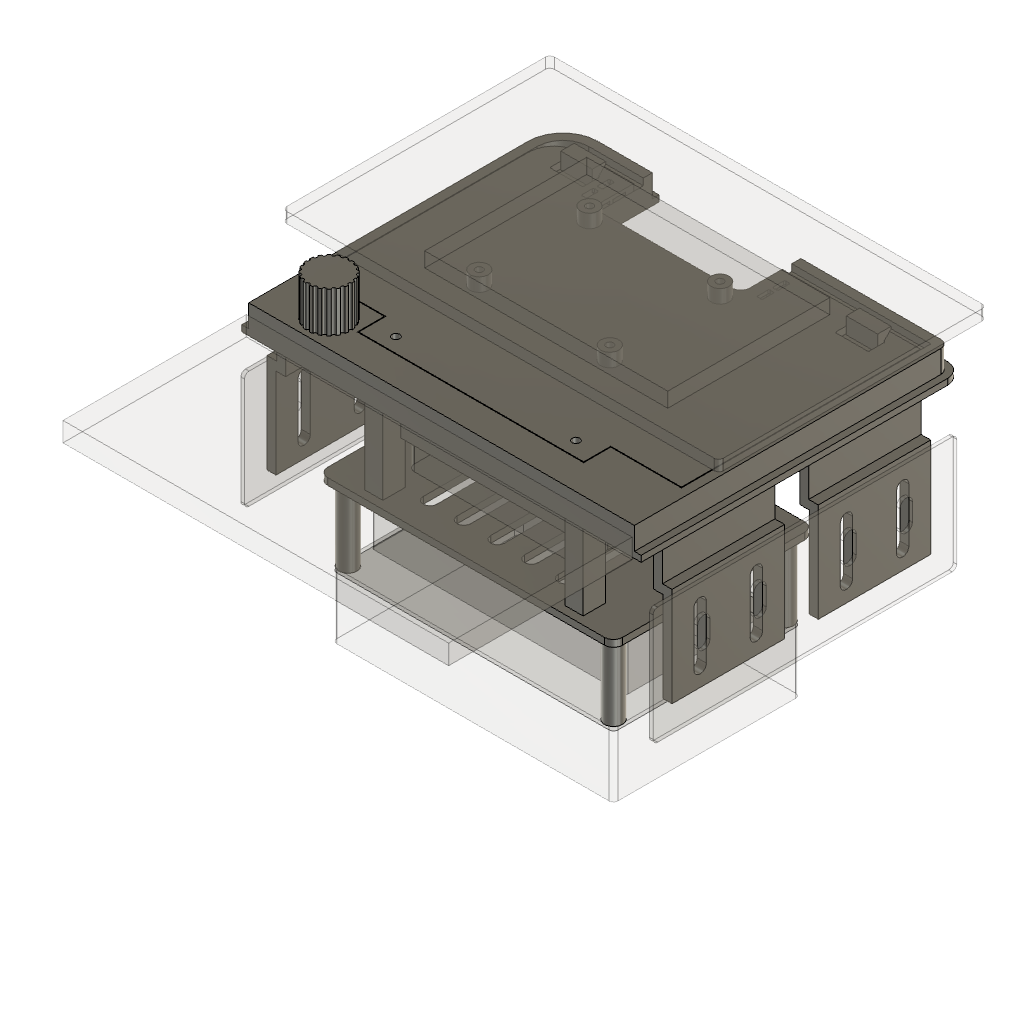
baja-dash-case (Autodesk Fusion 360 design; units mm, degrees)
part number: 2026-11-05-16-55-25-787
part number: 2026-11-05-16-55-25-887
part number: 2026-11-05-16-55-26-323
part number: 2026-11-05-16-55-27-474
part number: 2026-11-05-16-55-28-006
part number: 2026-11-05-16-55-28-400
part number: 2026-11-05-16-55-28-827
part number: 2026-11-05-16-55-29-301
part number: 2026-11-05-16-55-29-835
part number: 2026-11-05-16-55-32-602
part number: 2026-11-05-16-55-34-202
part number: 2026-11-05-16-55-34-630
part number: 2026-11-05-16-55-35-112
part number: 2026-11-05-16-55-35-616
part number: 2026-11-05-16-55-35-892
part number: 2026-11-05-16-55-36-122
Autodesk Fusion 360 part; units mm, degrees
(part 1 of 2)
ref_plane "WorkPlane1" through (0, 0, 6.35) normal (0, 0, 1) x (1, 0, 0) in component "Dash panel"
sketch "Sketch1" plane through (0, 0, 6.35) normal (0, 0, 1) x (1, 0, 0) in component "Dash panel"
  line L0 (0, 82.55) -> (171.45, 82.55)
  line L1 (171.45, 82.55) -> (171.45, 218.75)
  arc A0 (171.45, 218.75) -> (167.95, 222.25) centre (167.95, 218.75) ccw
  line L2 (167.95, 222.25) -> (15.5, 222.25)
  arc A1 (15.5, 222.25) -> (0, 206.75) centre (15.5, 206.75) ccw
  line L3 (0, 206.75) -> (0, 82.55)
extrude "Panel" add sketch "Sketch1" along normal mid plane 12.7 makes body 1 in component "Dash panel"
ref_plane "WorkPlane2" through (0, 0, 1.35) normal (0, 0, 1) x (1, 0, 0) in component "Dash panel"
sketch "Sketch2" plane through (0, 0, 1.35) normal (0, 0, 1) x (1, 0, 0) in component "Dash panel"
  line L0 (-3, 82.55) -> (174.45, 82.55)
  line L1 (174.45, 82.55) -> (174.45, 218.75)
  arc A0 (174.45, 218.75) -> (167.95, 225.25) centre (167.95, 218.75) ccw
  line L2 (167.95, 225.25) -> (-3, 225.25)
  line L3 (-3, 225.25) -> (-3, 82.55)
extrude "Lip" add sketch "Sketch2" along normal mid plane 2.7 bodies 1 in component "Dash panel"
ref_plane "WorkPlane3" through (0, 0, 11.7) normal (0, 0, 1) x (1, 0, 0) in component "Dash panel"
sketch "Sketch3" plane through (0, 0, 11.7) normal (0, 0, 1) x (1, 0, 0) in component "Dash panel"
  line L0 (4, 107.45) -> (35.425, 107.45)
  line L1 (35.425, 107.45) -> (35.425, 95.45)
  line L2 (35.425, 95.45) -> (136.025, 95.45)
  line L3 (136.025, 95.45) -> (136.025, 107.45)
  line L4 (136.025, 107.45) -> (167.45, 107.45)
  line L5 (167.45, 107.45) -> (167.45, 218.25)
  line L6 (167.45, 218.25) -> (15.5, 218.25)
  arc A0 (15.5, 218.25) -> (4, 206.75) centre (15.5, 206.75) ccw
  line L7 (4, 206.75) -> (4, 107.45)
extrude "Carrier pocket" cut sketch "Sketch3" along normal mid plane 4 bodies 1 in component "Dash panel"
ref_plane "WorkPlane4" through (22.3, 0, 0) normal (1, 0, 0) x (0, 1, 0) in component "Dash panel"
sketch "Sketch4" plane through (22.3, 0, 0) normal (1, 0, 0) x (0, 0, -1) in component "Dash panel"
  line L0 (-9.2, 205.95) -> (-9.2, 208.95)
  line L1 (-9.2, 208.95) -> (-13, 208.95)
  line L2 (-13, 208.95) -> (-16, 211.95)
  line L3 (-16, 211.95) -> (-17, 211.95)
  line L4 (-17, 211.95) -> (-17, 205.95)
  line L5 (-17, 205.95) -> (-9.2, 205.95)
extrude "Carrier hook" add sketch "Sketch4" along normal mid plane 14 bodies 1 in component "Dash panel"
ref_plane "WorkPlane5" through (149.15, 0, 0) normal (1, 0, 0) x (0, 1, 0) in component "Dash panel"
sketch "Sketch5" plane through (149.15, 0, 0) normal (1, 0, 0) x (0, 0, -1) in component "Dash panel"
  line L0 (-9.2, 205.95) -> (-9.2, 208.95)
  line L1 (-9.2, 208.95) -> (-13, 208.95)
  line L2 (-13, 208.95) -> (-16, 211.95)
  line L3 (-16, 211.95) -> (-17, 211.95)
  line L4 (-17, 211.95) -> (-17, 205.95)
  line L5 (-17, 205.95) -> (-9.2, 205.95)
extrude "Carrier hook (1)" add sketch "Sketch5" along normal mid plane 14 bodies 1 in component "Dash panel"
ref_plane "WorkPlane6" through (0, 0, 7.95) normal (0, 0, 1) x (1, 0, 0) in component "Dash panel"
sketch "Sketch6" plane through (0, 0, 7.95) normal (0, 0, 1) x (1, 0, 0) in component "Dash panel"
  circle A0 centre (45.725, 102.25) radius 2
  circle A1 centre (125.725, 102.25) radius 2
extrude "Lock screw inserts" cut sketch "Sketch6" along normal mid plane 9.5 bodies 1 in component "Dash panel"
ref_plane "WorkPlane7" through (0, 0, 6.35) normal (0, 0, 1) x (1, 0, 0) in component "Dash panel"
sketch "Sketch7" plane through (0, 0, 6.35) normal (0, 0, 1) x (1, 0, 0) in component "Dash panel"
  line L0 (43.725, 195.54) -> (101.725, 195.54)
  arc A0 (101.725, 195.54) -> (105.725, 199.54) centre (101.725, 199.54) ccw
  line L1 (105.725, 199.54) -> (105.725, 230.25)
  line L2 (105.725, 230.25) -> (39.725, 230.25)
  line L3 (39.725, 230.25) -> (39.725, 199.54)
  arc A1 (39.725, 199.54) -> (43.725, 195.54) centre (43.725, 199.54) ccw
extrude "Cable notch" cut sketch "Sketch7" along normal mid plane 14.7 bodies 1 in component "Dash panel"
ref_plane "WorkPlane8" through (0, 0, 4.6) normal (0, 0, 1) x (1, 0, 0) in component "Dash panel"
sketch "Sketch8" plane through (0, 0, 4.6) normal (0, 0, 1) x (1, 0, 0) in component "Dash panel"
  line L0 (18.5, 85.8) -> (31.5, 85.8)
  arc A0 (31.5, 85.8) -> (32.5, 86.8) centre (31.5, 86.8) ccw
  line L1 (32.5, 86.8) -> (32.5, 99.8)
  arc A1 (32.5, 99.8) -> (31.5, 100.8) centre (31.5, 99.8) ccw
  line L2 (31.5, 100.8) -> (18.5, 100.8)
  arc A2 (18.5, 100.8) -> (17.5, 99.8) centre (18.5, 99.8) ccw
  line L3 (17.5, 99.8) -> (17.5, 86.8)
  arc A3 (17.5, 86.8) -> (18.5, 85.8) centre (18.5, 86.8) ccw
extrude "Encoder pocket" cut sketch "Sketch8" along normal mid plane 11.2 bodies 1 in component "Dash panel"
ref_plane "WorkPlane9" through (0, 0, 6.35) normal (0, 0, 1) x (1, 0, 0) in component "Dash panel"
sketch "Sketch9" plane through (0, 0, 6.35) normal (0, 0, 1) x (1, 0, 0) in component "Dash panel"
  circle A0 centre (25, 93.3) radius 3.7
extrude "Encoder collar hole" cut sketch "Sketch9" along normal mid plane 14.7 bodies 1 in component "Dash panel"
ref_plane "WorkPlane10" through (0, 0, 2.75) normal (0, 0, 1) x (1, 0, 0) in component "Dash panel"
sketch "Sketch10" plane through (0, 0, 2.75) normal (0, 0, 1) x (1, 0, 0) in component "Dash panel"
  circle A0 centre (8, 103) radius 2
  circle A1 centre (8, 137) radius 2
  circle A2 centre (8, 168) radius 2
  circle A3 centre (8, 202) radius 2
  circle A4 centre (163.45, 103) radius 2
  circle A5 centre (163.45, 137) radius 2
  circle A6 centre (163.45, 168) radius 2
  circle A7 centre (163.45, 202) radius 2
  circle A8 centre (32.2, 120) radius 2
  circle A9 centre (32.2, 156) radius 2
  circle A10 centre (139.2, 120) radius 2
  circle A11 centre (139.2, 156) radius 2
extrude "Heat-set insert holes" cut sketch "Sketch10" along normal mid plane 7.5 bodies 1 in component "Dash panel"
ref_plane "WorkPlane1" through (0, 0, 11.2) normal (0, 0, 1) x (1, 0, 0) in component "Screen carrier"
sketch "Sketch1 (2)" plane through (0, 0, 11.2) normal (0, 0, 1) x (1, 0, 0) in component "Screen carrier"
  line L0 (4.3, 107.75) -> (35.725, 107.75)
  line L1 (35.725, 107.75) -> (35.725, 95.75)
  line L2 (35.725, 95.75) -> (135.725, 95.75)
  line L3 (135.725, 95.75) -> (135.725, 107.75)
  line L4 (135.725, 107.75) -> (167.15, 107.75)
  line L5 (167.15, 107.75) -> (167.15, 213.95)
  line L6 (167.15, 213.95) -> (15.5, 213.95)
  arc A0 (15.5, 213.95) -> (4.3, 202.75) centre (15.5, 202.75) ccw
  line L7 (4.3, 202.75) -> (4.3, 107.75)
extrude "Carrier" add sketch "Sketch1 (2)" along normal mid plane 3 separate body makes body 2 in component "Screen carrier"
ref_plane "WorkPlane2" through (0, 0, 15.45) normal (0, 0, 1) x (1, 0, 0) in component "Screen carrier"
sketch "Sketch2 (2)" plane through (0, 0, 15.45) normal (0, 0, 1) x (1, 0, 0) in component "Screen carrier"
  circle A0 centre (44.515, 140.54) radius 4
extrude "Screen post" add sketch "Sketch2 (2)" along normal mid plane 6.5 bodies 2 in component "Screen carrier"
ref_plane "WorkPlane3" through (0, 0, 15.45) normal (0, 0, 1) x (1, 0, 0) in component "Screen carrier"
sketch "Sketch3 (2)" plane through (0, 0, 15.45) normal (0, 0, 1) x (1, 0, 0) in component "Screen carrier"
  circle A0 centre (102.515, 140.54) radius 4
extrude "Screen post (1)" add sketch "Sketch3 (2)" along normal mid plane 6.5 bodies 2 in component "Screen carrier"
ref_plane "WorkPlane4" through (0, 0, 15.45) normal (0, 0, 1) x (1, 0, 0) in component "Screen carrier"
sketch "Sketch4 (2)" plane through (0, 0, 15.45) normal (0, 0, 1) x (1, 0, 0) in component "Screen carrier"
  circle A0 centre (44.515, 189.54) radius 4
extrude "Screen post (2)" add sketch "Sketch4 (2)" along normal mid plane 6.5 bodies 2 in component "Screen carrier"
ref_plane "WorkPlane5" through (0, 0, 15.45) normal (0, 0, 1) x (1, 0, 0) in component "Screen carrier"
sketch "Sketch5 (2)" plane through (0, 0, 15.45) normal (0, 0, 1) x (1, 0, 0) in component "Screen carrier"
  circle A0 centre (102.515, 189.54) radius 4
extrude "Screen post (3)" add sketch "Sketch5 (2)" along normal mid plane 6.5 bodies 2 in component "Screen carrier"
ref_plane "WorkPlane6" through (0, 0, 14.2) normal (0, 0, 1) x (1, 0, 0) in component "Screen carrier"
sketch "Sketch6 (2)" plane through (0, 0, 14.2) normal (0, 0, 1) x (1, 0, 0) in component "Screen carrier"
  circle A0 centre (44.515, 140.54) radius 1.6
  circle A1 centre (102.515, 140.54) radius 1.6
  circle A2 centre (44.515, 189.54) radius 1.6
  circle A3 centre (102.515, 189.54) radius 1.6
extrude "Screen screw holes" cut sketch "Sketch6 (2)" along normal mid plane 11 bodies 2 in component "Screen carrier"
ref_plane "WorkPlane7" through (0, 0, 11.2) normal (0, 0, 1) x (1, 0, 0) in component "Screen carrier"
sketch "Sketch7 (2)" plane through (0, 0, 11.2) normal (0, 0, 1) x (1, 0, 0) in component "Screen carrier"
  circle A0 centre (44.515, 140.54) radius 2.75
extrude "Screw counterbore" cut sketch "Sketch7 (2)" along normal mid plane 5 bodies 2 in component "Screen carrier"
ref_plane "WorkPlane8" through (0, 0, 11.2) normal (0, 0, 1) x (1, 0, 0) in component "Screen carrier"
sketch "Sketch8 (2)" plane through (0, 0, 11.2) normal (0, 0, 1) x (1, 0, 0) in component "Screen carrier"
  circle A0 centre (102.515, 140.54) radius 2.75
extrude "Screw counterbore (1)" cut sketch "Sketch8 (2)" along normal mid plane 5 bodies 2 in component "Screen carrier"
ref_plane "WorkPlane9" through (0, 0, 11.2) normal (0, 0, 1) x (1, 0, 0) in component "Screen carrier"
sketch "Sketch9 (2)" plane through (0, 0, 11.2) normal (0, 0, 1) x (1, 0, 0) in component "Screen carrier"
  circle A0 centre (44.515, 189.54) radius 2.75
extrude "Screw counterbore (2)" cut sketch "Sketch9 (2)" along normal mid plane 5 bodies 2 in component "Screen carrier"
ref_plane "WorkPlane10" through (0, 0, 11.2) normal (0, 0, 1) x (1, 0, 0) in component "Screen carrier"
sketch "Sketch10 (2)" plane through (0, 0, 11.2) normal (0, 0, 1) x (1, 0, 0) in component "Screen carrier"
  circle A0 centre (102.515, 189.54) radius 2.75
extrude "Screw counterbore (3)" cut sketch "Sketch10 (2)" along normal mid plane 5 bodies 2 in component "Screen carrier"
ref_plane "WorkPlane11" through (0, 0, 11.2) normal (0, 0, 1) x (1, 0, 0) in component "Screen carrier"
sketch "Sketch11" plane through (0, 0, 11.2) normal (0, 0, 1) x (1, 0, 0) in component "Screen carrier"
  line L0 (15.4, 201.45) -> (29.2, 201.45)
  arc A0 (29.2, 201.45) -> (29.7, 201.95) centre (29.2, 201.95) ccw
  line L1 (29.7, 201.95) -> (29.7, 208.45)
  arc A1 (29.7, 208.45) -> (29.2, 208.95) centre (29.2, 208.45) ccw
  line L2 (29.2, 208.95) -> (15.4, 208.95)
  arc A2 (15.4, 208.95) -> (14.9, 208.45) centre (15.4, 208.45) ccw
  line L3 (14.9, 208.45) -> (14.9, 201.95)
  arc A3 (14.9, 201.95) -> (15.4, 201.45) centre (15.4, 201.95) ccw
  line L4 (142.25, 201.45) -> (156.05, 201.45)
  arc A4 (156.05, 201.45) -> (156.55, 201.95) centre (156.05, 201.95) ccw
  line L5 (156.55, 201.95) -> (156.55, 208.45)
  arc A5 (156.55, 208.45) -> (156.05, 208.95) centre (156.05, 208.45) ccw
  line L6 (156.05, 208.95) -> (142.25, 208.95)
  arc A6 (142.25, 208.95) -> (141.75, 208.45) centre (142.25, 208.45) ccw
  line L7 (141.75, 208.45) -> (141.75, 201.95)
  arc A7 (141.75, 201.95) -> (142.25, 201.45) centre (142.25, 201.95) ccw
extrude "Hook slots" cut sketch "Sketch11" along normal mid plane 5 bodies 2 in component "Screen carrier"
ref_plane "WorkPlane12" through (0, 0, 11.2) normal (0, 0, 1) x (1, 0, 0) in component "Screen carrier"
sketch "Sketch12" plane through (0, 0, 11.2) normal (0, 0, 1) x (1, 0, 0) in component "Screen carrier"
  circle A0 centre (45.725, 102.25) radius 1.7
  circle A1 centre (125.725, 102.25) radius 1.7
extrude "Lock screw holes" cut sketch "Sketch12" along normal mid plane 5 bodies 2 in component "Screen carrier"
ref_plane "WorkPlane13" through (0, 0, 11.2) normal (0, 0, 1) x (1, 0, 0) in component "Screen carrier"
sketch "Sketch13" plane through (0, 0, 11.2) normal (0, 0, 1) x (1, 0, 0) in component "Screen carrier"
  line L0 (43.725, 195.54) -> (101.725, 195.54)
  arc A0 (101.725, 195.54) -> (105.725, 199.54) centre (101.725, 199.54) ccw
  line L1 (105.725, 199.54) -> (105.725, 218.95)
  line L2 (105.725, 218.95) -> (39.725, 218.95)
  line L3 (39.725, 218.95) -> (39.725, 199.54)
  arc A1 (39.725, 199.54) -> (43.725, 195.54) centre (43.725, 199.54) ccw
extrude "Cable notch'" cut sketch "Sketch13" along normal mid plane 5 bodies 2 in component "Screen carrier"
ref_plane "WorkPlane14" through (0, 0, 11.2) normal (0, 0, 1) x (1, 0, 0) in component "Screen carrier"
sketch "Sketch14" plane through (0, 0, 11.2) normal (0, 0, 1) x (1, 0, 0) in component "Screen carrier"
  line L0 (33.025, 197.79) -> (34.425, 197.79)
  arc A0 (34.425, 197.79) -> (34.925, 198.29) centre (34.425, 198.29) ccw
  line L1 (34.925, 198.29) -> (34.925, 202.79)
  arc A1 (34.925, 202.79) -> (34.425, 203.29) centre (34.425, 202.79) ccw
  line L2 (34.425, 203.29) -> (33.025, 203.29)
  arc A2 (33.025, 203.29) -> (32.525, 202.79) centre (33.025, 202.79) ccw
  line L3 (32.525, 202.79) -> (32.525, 198.29)
  arc A3 (32.525, 198.29) -> (33.025, 197.79) centre (33.025, 198.29) ccw
  line L4 (33.025, 204.79) -> (34.425, 204.79)
  arc A4 (34.425, 204.79) -> (34.925, 205.29) centre (34.425, 205.29) ccw
  line L5 (34.925, 205.29) -> (34.925, 209.79)
  arc A5 (34.925, 209.79) -> (34.425, 210.29) centre (34.425, 209.79) ccw
  line L6 (34.425, 210.29) -> (33.025, 210.29)
  arc A6 (33.025, 210.29) -> (32.525, 209.79) centre (33.025, 209.79) ccw
  line L7 (32.525, 209.79) -> (32.525, 205.29)
  arc A7 (32.525, 205.29) -> (33.025, 204.79) centre (33.025, 205.29) ccw
  line L8 (111.025, 197.79) -> (112.425, 197.79)
  arc A8 (112.425, 197.79) -> (112.925, 198.29) centre (112.425, 198.29) ccw
  line L9 (112.925, 198.29) -> (112.925, 202.79)
  arc A9 (112.925, 202.79) -> (112.425, 203.29) centre (112.425, 202.79) ccw
  line L10 (112.425, 203.29) -> (111.025, 203.29)
  arc A10 (111.025, 203.29) -> (110.525, 202.79) centre (111.025, 202.79) ccw
  line L11 (110.525, 202.79) -> (110.525, 198.29)
  arc A11 (110.525, 198.29) -> (111.025, 197.79) centre (111.025, 198.29) ccw
  line L12 (111.025, 204.79) -> (112.425, 204.79)
  arc A12 (112.425, 204.79) -> (112.925, 205.29) centre (112.425, 205.29) ccw
  line L13 (112.925, 205.29) -> (112.925, 209.79)
  arc A13 (112.925, 209.79) -> (112.425, 210.29) centre (112.425, 209.79) ccw
  line L14 (112.425, 210.29) -> (111.025, 210.29)
  arc A14 (111.025, 210.29) -> (110.525, 209.79) centre (111.025, 209.79) ccw
  line L15 (110.525, 209.79) -> (110.525, 205.29)
  arc A15 (110.525, 205.29) -> (111.025, 204.79) centre (111.025, 205.29) ccw
extrude "Zip-tie slots" cut sketch "Sketch14" along normal mid plane 5 bodies 2 in component "Screen carrier"
ref_plane "WorkPlane15" through (0, 0, 9.95) normal (0, 0, 1) x (1, 0, 0) in component "Screen carrier"
sketch "Sketch15" plane through (0, 0, 9.95) normal (0, 0, 1) x (1, 0, 0) in component "Screen carrier"
  line L0 (32.525, 197.79) -> (40.925, 197.79)
  line L1 (40.925, 197.79) -> (40.925, 203.29)
  line L2 (40.925, 203.29) -> (32.525, 203.29)
  line L3 (32.525, 203.29) -> (32.525, 197.79)
  line L4 (32.525, 204.79) -> (40.925, 204.79)
  line L5 (40.925, 204.79) -> (40.925, 210.29)
  line L6 (40.925, 210.29) -> (32.525, 210.29)
  line L7 (32.525, 210.29) -> (32.525, 204.79)
  line L8 (104.525, 197.79) -> (112.925, 197.79)
  line L9 (112.925, 197.79) -> (112.925, 203.29)
  line L10 (112.925, 203.29) -> (104.525, 203.29)
  line L11 (104.525, 203.29) -> (104.525, 197.79)
  line L12 (104.525, 204.79) -> (112.925, 204.79)
  line L13 (112.925, 204.79) -> (112.925, 210.29)
  line L14 (112.925, 210.29) -> (104.525, 210.29)
  line L15 (104.525, 210.29) -> (104.525, 204.79)
extrude "Zip-tie grooves" cut sketch "Sketch15" along normal mid plane 2.5 bodies 2 in component "Screen carrier"
ref_plane "WorkPlane1" through (0, 0, 22.7) normal (0, 0, 1) x (1, 0, 0) in component "Volume knob"
sketch "Sketch1 (3)" plane through (0, 0, 22.7) normal (0, 0, 1) x (1, 0, 0) in component "Volume knob"
  circle A0 centre (25, 93.3) radius 9.5
extrude "Knob" add sketch "Sketch1 (3)" along normal mid plane 18 separate body makes body 3 in component "Volume knob"
ref_plane "WorkPlane2" through (0, 0, 22.7) normal (0, 0, 1) x (1, 0, 0) in component "Volume knob"
sketch "Sketch2 (3)" plane through (0, 0, 22.7) normal (0, 0, 1) x (1, 0, 0) in component "Volume knob"
  circle A0 centre (34.5, 93.3) radius 0.8
  circle A1 centre (34.035, 96.2357) radius 0.8
  circle A2 centre (32.6857, 98.884) radius 0.8
  circle A3 centre (30.584, 100.9857) radius 0.8
  circle A4 centre (27.9357, 102.335) radius 0.8
  circle A5 centre (25, 102.8) radius 0.8
  circle A6 centre (22.0643, 102.335) radius 0.8
  circle A7 centre (19.416, 100.9857) radius 0.8
  circle A8 centre (17.3143, 98.884) radius 0.8
  circle A9 centre (15.965, 96.2357) radius 0.8
  circle A10 centre (15.5, 93.3) radius 0.8
  circle A11 centre (15.965, 90.3643) radius 0.8
  circle A12 centre (17.3143, 87.716) radius 0.8
  circle A13 centre (19.416, 85.6143) radius 0.8
  circle A14 centre (22.0643, 84.265) radius 0.8
  circle A15 centre (25, 83.8) radius 0.8
  circle A16 centre (27.9357, 84.265) radius 0.8
  circle A17 centre (30.584, 85.6143) radius 0.8
  circle A18 centre (32.6857, 87.716) radius 0.8
  circle A19 centre (34.035, 90.3643) radius 0.8
extrude "Grip" cut sketch "Sketch2 (3)" along normal mid plane 20 bodies 3 in component "Volume knob"
ref_plane "WorkPlane3" through (0, 0, 14.7) normal (0, 0, 1) x (1, 0, 0) in component "Volume knob"
sketch "Sketch3 (3)" plane through (0, 0, 14.7) normal (0, 0, 1) x (1, 0, 0) in component "Volume knob"
  circle A0 centre (25, 93.3) radius 6.25
extrude "Nut recess" cut sketch "Sketch3 (3)" along normal mid plane 4 bodies 3 in component "Volume knob"
ref_plane "WorkPlane4" through (0, 0, 16.705) normal (0, 0, 1) x (1, 0, 0) in component "Volume knob"
sketch "Sketch4 (3)" plane through (0, 0, 16.705) normal (0, 0, 1) x (1, 0, 0) in component "Volume knob"
  circle A0 centre (25, 93.3) radius 3.75
extrude "Shaft clearance" cut sketch "Sketch4 (3)" along normal mid plane 8.01 bodies 3 in component "Volume knob"
ref_plane "WorkPlane5" through (0, 0, 25.7) normal (0, 0, 1) x (1, 0, 0) in component "Volume knob"
sketch "Sketch5 (3)" plane through (0, 0, 25.7) normal (0, 0, 1) x (1, 0, 0) in component "Volume knob"
  line L0 (22.3732, 94.85) -> (27.6268, 94.85)
  arc A0 (22.3732, 94.85) -> (27.6268, 94.85) centre (25, 93.3) ccw
extrude "D bore" cut sketch "Sketch5 (3)" along normal mid plane 10 bodies 3 in component "Volume knob"
ref_plane "WorkPlane1" through (0, 120, 0) normal (0, 1, 0) x (0, 0, 1) in component "Adapter plate lower left"
sketch "Sketch1 (4)" plane through (0, 120, 0) normal (0, 1, 0) x (1, 0, 0) in component "Adapter plate lower left"
  line L0 (16, 0) -> (0, 0)
  line L1 (0, 0) -> (0, 16)
  line L2 (0, 16) -> (-4.275, 16)
  line L3 (-4.275, 16) -> (-4.275, 60)
  line L4 (-4.275, 60) -> (-0.275, 60)
  line L5 (-0.275, 60) -> (-0.275, 20)
  line L6 (-0.275, 20) -> (4, 20)
  line L7 (4, 20) -> (4, 4)
  line L8 (4, 4) -> (16, 4)
  line L9 (16, 4) -> (16, 0)
extrude "Adapter" add sketch "Sketch1 (4)" along normal mid plane 50 separate body makes body 4 in component "Adapter plate lower left"
ref_plane "WorkPlane2" through (0, 0, -2) normal (0, 0, 1) x (1, 0, 0) in component "Adapter plate lower left"
sketch "Sketch2 (4)" plane through (0, 0, -2) normal (0, 0, 1) x (1, 0, 0) in component "Adapter plate lower left"
  circle A0 centre (8, 103) radius 1.7
  circle A1 centre (8, 137) radius 1.7
extrude "Panel screw holes" cut sketch "Sketch2 (4)" along normal mid plane 6 bodies 4 in component "Adapter plate lower left"
ref_plane "WorkPlane3" through (-2.275, 0, 0) normal (1, 0, 0) x (0, 1, 0) in component "Adapter plate lower left"
sketch "Sketch3 (4)" plane through (-2.275, 0, 0) normal (1, 0, 0) x (0, 0, -1) in component "Adapter plate lower left"
  line L0 (52, 104.75) -> (28, 104.75)
  arc A0 (28, 110.25) -> (28, 104.75) centre (28, 107.5) ccw
  line L1 (28, 110.25) -> (52, 110.25)
  arc A1 (52, 104.75) -> (52, 110.25) centre (52, 107.5) ccw
extrude "Bracket slot" cut sketch "Sketch3 (4)" along normal mid plane 8 bodies 4 in component "Adapter plate lower left"
ref_plane "WorkPlane4" through (-2.275, 0, 0) normal (1, 0, 0) x (0, 1, 0) in component "Adapter plate lower left"
sketch "Sketch4 (4)" plane through (-2.275, 0, 0) normal (1, 0, 0) x (0, 0, -1) in component "Adapter plate lower left"
  line L0 (52, 129.75) -> (28, 129.75)
  arc A0 (28, 135.25) -> (28, 129.75) centre (28, 132.5) ccw
  line L1 (28, 135.25) -> (52, 135.25)
  arc A1 (52, 129.75) -> (52, 135.25) centre (52, 132.5) ccw
extrude "Bracket slot (1)" cut sketch "Sketch4 (4)" along normal mid plane 8 bodies 4 in component "Adapter plate lower left"
ref_plane "WorkPlane1" through (0, 185, 0) normal (0, 1, 0) x (0, 0, 1) in component "Adapter plate upper left"
sketch "Sketch1 (5)" plane through (0, 185, 0) normal (0, 1, 0) x (1, 0, 0) in component "Adapter plate upper left"
  line L0 (16, 0) -> (0, 0)
  line L1 (0, 0) -> (0, 16)
  line L2 (0, 16) -> (-4.275, 16)
  line L3 (-4.275, 16) -> (-4.275, 60)
  line L4 (-4.275, 60) -> (-0.275, 60)
  line L5 (-0.275, 60) -> (-0.275, 20)
  line L6 (-0.275, 20) -> (4, 20)
  line L7 (4, 20) -> (4, 4)
  line L8 (4, 4) -> (16, 4)
  line L9 (16, 4) -> (16, 0)
extrude "Adapter'" add sketch "Sketch1 (5)" along normal mid plane 50 separate body makes body 5 in component "Adapter plate upper left"
ref_plane "WorkPlane2" through (0, 0, -2) normal (0, 0, 1) x (1, 0, 0) in component "Adapter plate upper left"
sketch "Sketch2 (5)" plane through (0, 0, -2) normal (0, 0, 1) x (1, 0, 0) in component "Adapter plate upper left"
  circle A0 centre (8, 168) radius 1.7
  circle A1 centre (8, 202) radius 1.7
extrude "Panel screw holes'" cut sketch "Sketch2 (5)" along normal mid plane 6 bodies 5 in component "Adapter plate upper left"
ref_plane "WorkPlane3" through (-2.275, 0, 0) normal (1, 0, 0) x (0, 1, 0) in component "Adapter plate upper left"
sketch "Sketch3 (5)" plane through (-2.275, 0, 0) normal (1, 0, 0) x (0, 0, -1) in component "Adapter plate upper left"
  line L0 (52, 169.75) -> (28, 169.75)
  arc A0 (28, 175.25) -> (28, 169.75) centre (28, 172.5) ccw
  line L1 (28, 175.25) -> (52, 175.25)
  arc A1 (52, 169.75) -> (52, 175.25) centre (52, 172.5) ccw
extrude "Bracket slot'" cut sketch "Sketch3 (5)" along normal mid plane 8 bodies 5 in component "Adapter plate upper left"
ref_plane "WorkPlane4" through (-2.275, 0, 0) normal (1, 0, 0) x (0, 1, 0) in component "Adapter plate upper left"
sketch "Sketch4 (5)" plane through (-2.275, 0, 0) normal (1, 0, 0) x (0, 0, -1) in component "Adapter plate upper left"
  line L0 (52, 194.75) -> (28, 194.75)
  arc A0 (28, 200.25) -> (28, 194.75) centre (28, 197.5) ccw
  line L1 (28, 200.25) -> (52, 200.25)
  arc A1 (52, 194.75) -> (52, 200.25) centre (52, 197.5) ccw
extrude "Bracket slot (1)'" cut sketch "Sketch4 (5)" along normal mid plane 8 bodies 5 in component "Adapter plate upper left"
ref_plane "WorkPlane1" through (0, 120, 0) normal (0, 1, 0) x (0, 0, 1) in component "Adapter plate lower right"
sketch "Sketch1 (6)" plane through (0, 120, 0) normal (0, 1, 0) x (1, 0, 0) in component "Adapter plate lower right"
  line L0 (155.45, 0) -> (171.45, 0)
  line L1 (171.45, 0) -> (171.45, 16)
  line L2 (171.45, 16) -> (175.725, 16)
  line L3 (175.725, 16) -> (175.725, 60)
  line L4 (175.725, 60) -> (171.725, 60)
  line L5 (171.725, 60) -> (171.725, 20)
  line L6 (171.725, 20) -> (167.45, 20)
  line L7 (167.45, 20) -> (167.45, 4)
  line L8 (167.45, 4) -> (155.45, 4)
  line L9 (155.45, 4) -> (155.45, 0)
extrude "Adapter''" add sketch "Sketch1 (6)" along normal mid plane 50 separate body makes body 6 in component "Adapter plate lower right"
ref_plane "WorkPlane2" through (0, 0, -2) normal (0, 0, 1) x (1, 0, 0) in component "Adapter plate lower right"
sketch "Sketch2 (6)" plane through (0, 0, -2) normal (0, 0, 1) x (1, 0, 0) in component "Adapter plate lower right"
  circle A0 centre (163.45, 103) radius 1.7
  circle A1 centre (163.45, 137) radius 1.7
extrude "Panel screw holes''" cut sketch "Sketch2 (6)" along normal mid plane 6 bodies 6 in component "Adapter plate lower right"
ref_plane "WorkPlane3" through (173.725, 0, 0) normal (1, 0, 0) x (0, 1, 0) in component "Adapter plate lower right"
sketch "Sketch3 (6)" plane through (173.725, 0, 0) normal (1, 0, 0) x (0, 0, -1) in component "Adapter plate lower right"
  line L0 (52, 104.75) -> (28, 104.75)
  arc A0 (28, 110.25) -> (28, 104.75) centre (28, 107.5) ccw
  line L1 (28, 110.25) -> (52, 110.25)
  arc A1 (52, 104.75) -> (52, 110.25) centre (52, 107.5) ccw
extrude "Bracket slot''" cut sketch "Sketch3 (6)" along normal mid plane 8 bodies 6 in component "Adapter plate lower right"
ref_plane "WorkPlane4" through (173.725, 0, 0) normal (1, 0, 0) x (0, 1, 0) in component "Adapter plate lower right"
sketch "Sketch4 (6)" plane through (173.725, 0, 0) normal (1, 0, 0) x (0, 0, -1) in component "Adapter plate lower right"
  line L0 (52, 129.75) -> (28, 129.75)
  arc A0 (28, 135.25) -> (28, 129.75) centre (28, 132.5) ccw
  line L1 (28, 135.25) -> (52, 135.25)
  arc A1 (52, 129.75) -> (52, 135.25) centre (52, 132.5) ccw
extrude "Bracket slot (1)''" cut sketch "Sketch4 (6)" along normal mid plane 8 bodies 6 in component "Adapter plate lower right"
ref_plane "WorkPlane1" through (0, 185, 0) normal (0, 1, 0) x (0, 0, 1) in component "Adapter plate upper right"
sketch "Sketch1 (7)" plane through (0, 185, 0) normal (0, 1, 0) x (1, 0, 0) in component "Adapter plate upper right"
  line L0 (155.45, 0) -> (171.45, 0)
  line L1 (171.45, 0) -> (171.45, 16)
  line L2 (171.45, 16) -> (175.725, 16)
  line L3 (175.725, 16) -> (175.725, 60)
  line L4 (175.725, 60) -> (171.725, 60)
  line L5 (171.725, 60) -> (171.725, 20)
  line L6 (171.725, 20) -> (167.45, 20)
  line L7 (167.45, 20) -> (167.45, 4)
  line L8 (167.45, 4) -> (155.45, 4)
  line L9 (155.45, 4) -> (155.45, 0)
extrude "Adapter'''" add sketch "Sketch1 (7)" along normal mid plane 50 separate body makes body 7 in component "Adapter plate upper right"
ref_plane "WorkPlane2" through (0, 0, -2) normal (0, 0, 1) x (1, 0, 0) in component "Adapter plate upper right"
sketch "Sketch2 (7)" plane through (0, 0, -2) normal (0, 0, 1) x (1, 0, 0) in component "Adapter plate upper right"
  circle A0 centre (163.45, 168) radius 1.7
  circle A1 centre (163.45, 202) radius 1.7
extrude "Panel screw holes'''" cut sketch "Sketch2 (7)" along normal mid plane 6 bodies 7 in component "Adapter plate upper right"
ref_plane "WorkPlane3" through (173.725, 0, 0) normal (1, 0, 0) x (0, 1, 0) in component "Adapter plate upper right"
sketch "Sketch3 (7)" plane through (173.725, 0, 0) normal (1, 0, 0) x (0, 0, -1) in component "Adapter plate upper right"
  line L0 (52, 169.75) -> (28, 169.75)
  arc A0 (28, 175.25) -> (28, 169.75) centre (28, 172.5) ccw
  line L1 (28, 175.25) -> (52, 175.25)
  arc A1 (52, 169.75) -> (52, 175.25) centre (52, 172.5) ccw
extrude "Bracket slot'''" cut sketch "Sketch3 (7)" along normal mid plane 8 bodies 7 in component "Adapter plate upper right"
ref_plane "WorkPlane4" through (173.725, 0, 0) normal (1, 0, 0) x (0, 1, 0) in component "Adapter plate upper right"
sketch "Sketch4 (7)" plane through (173.725, 0, 0) normal (1, 0, 0) x (0, 0, -1) in component "Adapter plate upper right"
  line L0 (52, 194.75) -> (28, 194.75)
  arc A0 (28, 200.25) -> (28, 194.75) centre (28, 197.5) ccw
  line L1 (28, 200.25) -> (52, 200.25)
  arc A1 (52, 194.75) -> (52, 200.25) centre (52, 197.5) ccw
extrude "Bracket slot (1)'''" cut sketch "Sketch4 (7)" along normal mid plane 8 bodies 7 in component "Adapter plate upper right"
ref_plane "WorkPlane1" through (0, 0, -1.5) normal (0, 0, 1) x (1, 0, 0) in component "Pi case"
sketch "Sketch1 (8)" plane through (0, 0, -1.5) normal (0, 0, 1) x (1, 0, 0) in component "Pi case"
  line L0 (40.2, 105) -> (131.2, 105)
  arc A0 (131.2, 105) -> (134.2, 108) centre (131.2, 108) ccw
  line L1 (134.2, 108) -> (134.2, 168)
  arc A1 (134.2, 168) -> (131.2, 171) centre (131.2, 168) ccw
  line L2 (131.2, 171) -> (40.2, 171)
  arc A2 (40.2, 171) -> (37.2, 168) centre (40.2, 168) ccw
  line L3 (37.2, 168) -> (37.2, 108)
  arc A3 (37.2, 108) -> (40.2, 105) centre (40.2, 108) ccw
extrude "Floor" add sketch "Sketch1 (8)" along normal mid plane 3 separate body makes body 8 in component "Pi case"
ref_plane "WorkPlane2" through (0, 0, -1.5) normal (0, 0, 1) x (1, 0, 0) in component "Pi case"
sketch "Sketch2 (8)" plane through (0, 0, -1.5) normal (0, 0, 1) x (1, 0, 0) in component "Pi case"
  line L0 (30.2, 112) -> (35.2, 112)
  arc A0 (35.2, 112) -> (38.2, 115) centre (35.2, 115) ccw
  line L1 (38.2, 115) -> (38.2, 161)
  arc A1 (38.2, 161) -> (35.2, 164) centre (35.2, 161) ccw
  line L2 (35.2, 164) -> (30.2, 164)
  arc A2 (30.2, 164) -> (27.2, 161) centre (30.2, 161) ccw
  line L3 (27.2, 161) -> (27.2, 115)
  arc A3 (27.2, 115) -> (30.2, 112) centre (30.2, 115) ccw
  line L4 (136.2, 112) -> (141.2, 112)
  arc A4 (141.2, 112) -> (144.2, 115) centre (141.2, 115) ccw
  line L5 (144.2, 115) -> (144.2, 161)
  arc A5 (144.2, 161) -> (141.2, 164) centre (141.2, 161) ccw
  line L6 (141.2, 164) -> (136.2, 164)
  arc A6 (136.2, 164) -> (133.2, 161) centre (136.2, 161) ccw
  line L7 (133.2, 161) -> (133.2, 115)
  arc A7 (133.2, 115) -> (136.2, 112) centre (136.2, 115) ccw
extrude "Ears" add sketch "Sketch2 (8)" along normal mid plane 3 bodies 8 in component "Pi case"
ref_plane "WorkPlane3" through (0, 0, -1.5) normal (0, 0, 1) x (1, 0, 0) in component "Pi case"
sketch "Sketch3 (8)" plane through (0, 0, -1.5) normal (0, 0, 1) x (1, 0, 0) in component "Pi case"
  circle A0 centre (32.2, 120) radius 1.7
  circle A1 centre (32.2, 156) radius 1.7
  circle A2 centre (139.2, 120) radius 1.7
  circle A3 centre (139.2, 156) radius 1.7
extrude "Panel screw holes''''" cut sketch "Sketch3 (8)" along normal mid plane 5 bodies 8 in component "Pi case"
ref_plane "WorkPlane4" through (0, 0, -15.25) normal (0, 0, 1) x (1, 0, 0) in component "Pi case"
sketch "Sketch4 (8)" plane through (0, 0, -15.25) normal (0, 0, 1) x (1, 0, 0) in component "Pi case"
  line L0 (40.2, 105) -> (131.2, 105)
  arc A0 (131.2, 105) -> (134.2, 108) centre (131.2, 108) ccw
  line L1 (134.2, 108) -> (134.2, 168)
  arc A1 (134.2, 168) -> (131.2, 171) centre (131.2, 168) ccw
  line L2 (131.2, 171) -> (40.2, 171)
  arc A2 (40.2, 171) -> (37.2, 168) centre (40.2, 168) ccw
  line L3 (37.2, 168) -> (37.2, 108)
  arc A3 (37.2, 108) -> (40.2, 105) centre (40.2, 108) ccw
  line L4 (40.2, 107) -> (131.2, 107)
  arc A4 (131.2, 107) -> (132.2, 108) centre (131.2, 108) ccw
  line L5 (132.2, 108) -> (132.2, 168)
  arc A5 (132.2, 168) -> (131.2, 169) centre (131.2, 168) ccw
  line L6 (131.2, 169) -> (40.2, 169)
  arc A6 (40.2, 169) -> (39.2, 168) centre (40.2, 168) ccw
  line L7 (39.2, 168) -> (39.2, 108)
  arc A7 (39.2, 108) -> (40.2, 107) centre (40.2, 108) ccw
extrude "Walls" add sketch "Sketch4 (8)" along normal mid plane 25.5 contours L0 A0 L1 A1 L2 A2 L3 A3 | L4 A4 L5 A5 L6 A6 L7 A7 bodies 8 in component "Pi case"
ref_plane "WorkPlane5" through (0, 0, -16) normal (0, 0, 1) x (1, 0, 0) in component "Pi case"
sketch "Sketch5 (4)" plane through (0, 0, -16) normal (0, 0, 1) x (1, 0, 0) in component "Pi case"
  line L0 (40.2, 107) -> (131.2, 107)
  arc A0 (131.2, 107) -> (132.2, 108) centre (131.2, 108) ccw
  line L1 (132.2, 108) -> (132.2, 168)
  arc A1 (132.2, 168) -> (131.2, 169) centre (131.2, 168) ccw
  line L2 (131.2, 169) -> (40.2, 169)
  arc A2 (40.2, 169) -> (39.2, 168) centre (40.2, 168) ccw
  line L3 (39.2, 168) -> (39.2, 108)
  arc A3 (39.2, 108) -> (40.2, 107) centre (40.2, 108) ccw
extrude "Inside" cut sketch "Sketch5 (4)" along normal mid plane 26 bodies 8 in component "Pi case"
ref_plane "WorkPlane6" through (0, 0, -5.75) normal (0, 0, 1) x (1, 0, 0) in component "Pi case"
sketch "Sketch6 (3)" plane through (0, 0, -5.75) normal (0, 0, 1) x (1, 0, 0) in component "Pi case"
  circle A0 centre (46.7, 113.5) radius 3.5
  circle A1 centre (104.7, 113.5) radius 3.5
  circle A2 centre (46.7, 162.5) radius 3.5
  circle A3 centre (104.7, 162.5) radius 3.5
extrude "Standoffs" add sketch "Sketch6 (3)" along normal mid plane 6.5 bodies 8 in component "Pi case"
ref_plane "WorkPlane7" through (0, 0, -6.75) normal (0, 0, 1) x (1, 0, 0) in component "Pi case"
sketch "Sketch7 (3)" plane through (0, 0, -6.75) normal (0, 0, 1) x (1, 0, 0) in component "Pi case"
  circle A0 centre (46.7, 113.5) radius 1.8
  circle A1 centre (104.7, 113.5) radius 1.8
  circle A2 centre (46.7, 162.5) radius 1.8
  circle A3 centre (104.7, 162.5) radius 1.8
extrude "Insert holes" cut sketch "Sketch7 (3)" along normal mid plane 6.5 bodies 8 in component "Pi case"
ref_plane "WorkPlane8" through (0, 0, -1.5) normal (0, 0, 1) x (1, 0, 0) in component "Pi case"
sketch "Sketch8 (3)" plane through (0, 0, -1.5) normal (0, 0, 1) x (1, 0, 0) in component "Pi case"
  line L0 (56.2, 120) -> (95.2, 120)
  arc A0 (95.2, 120) -> (98.2, 123) centre (95.2, 123) ccw
  line L1 (98.2, 123) -> (98.2, 153)
  arc A1 (98.2, 153) -> (95.2, 156) centre (95.2, 153) ccw
  line L2 (95.2, 156) -> (56.2, 156)
  arc A2 (56.2, 156) -> (53.2, 153) centre (56.2, 153) ccw
  line L3 (53.2, 153) -> (53.2, 123)
  arc A3 (53.2, 123) -> (56.2, 120) centre (56.2, 123) ccw
extrude "Vent" cut sketch "Sketch8 (3)" along normal mid plane 5 bodies 8 in component "Pi case"
ref_plane "WorkPlane9" through (133.2, 0, 0) normal (1, 0, 0) x (0, 1, 0) in component "Pi case"
sketch "Sketch9 (3)" plane through (133.2, 0, 0) normal (1, 0, 0) x (0, 0, -1) in component "Pi case"
  line L0 (30, 112.5) -> (30, 125.5)
  arc A0 (30, 125.5) -> (29, 126.5) centre (29, 125.5) ccw
  line L1 (29, 126.5) -> (9.4, 126.5)
  arc A1 (9.4, 126.5) -> (8.4, 125.5) centre (9.4, 125.5) ccw
  line L2 (8.4, 125.5) -> (8.4, 112.5)
  arc A2 (8.4, 112.5) -> (9.4, 111.5) centre (9.4, 112.5) ccw
  line L3 (9.4, 111.5) -> (29, 111.5)
  arc A3 (29, 111.5) -> (30, 112.5) centre (29, 112.5) ccw
  line L4 (30, 130.4) -> (30, 143.4)
  arc A4 (30, 143.4) -> (29, 144.4) centre (29, 143.4) ccw
  line L5 (29, 144.4) -> (9.4, 144.4)
  arc A5 (9.4, 144.4) -> (8.4, 143.4) centre (9.4, 143.4) ccw
  line L6 (8.4, 143.4) -> (8.4, 130.4)
  arc A6 (8.4, 130.4) -> (9.4, 129.4) centre (9.4, 130.4) ccw
  line L7 (9.4, 129.4) -> (29, 129.4)
  arc A7 (29, 129.4) -> (30, 130.4) centre (29, 130.4) ccw
  line L8 (30, 148.05) -> (30, 163.55)
  arc A8 (30, 163.55) -> (29, 164.55) centre (29, 163.55) ccw
  line L9 (29, 164.55) -> (9.4, 164.55)
  arc A9 (9.4, 164.55) -> (8.4, 163.55) centre (9.4, 163.55) ccw
  line L10 (8.4, 163.55) -> (8.4, 148.05)
  arc A10 (8.4, 148.05) -> (9.4, 147.05) centre (9.4, 148.05) ccw
  line L11 (9.4, 147.05) -> (29, 147.05)
  arc A11 (29, 147.05) -> (30, 148.05) centre (29, 148.05) ccw
extrude "USB and Ethernet" cut sketch "Sketch9 (3)" along normal mid plane 4 bodies 8 in component "Pi case"
ref_plane "WorkPlane10" through (0, 170, 0) normal (0, 1, 0) x (0, 0, 1) in component "Pi case"
sketch "Sketch10 (3)" plane through (0, 170, 0) normal (0, 1, 0) x (1, 0, 0) in component "Pi case"
  line L0 (48.4, 30) -> (88.4, 30)
  arc A0 (89.4, 29) -> (88.4, 30) centre (88.4, 29) ccw
  line L1 (89.4, 29) -> (89.4, 9.4)
  arc A1 (88.4, 8.4) -> (89.4, 9.4) centre (88.4, 9.4) ccw
  line L2 (88.4, 8.4) -> (48.4, 8.4)
  arc A2 (47.4, 9.4) -> (48.4, 8.4) centre (48.4, 9.4) ccw
  line L3 (47.4, 9.4) -> (47.4, 29)
  arc A3 (48.4, 30) -> (47.4, 29) centre (48.4, 29) ccw
extrude "Power and HDMI" cut sketch "Sketch10 (3)" along normal mid plane 4 bodies 8 in component "Pi case"
ref_plane "WorkPlane11" through (38.2, 0, 0) normal (1, 0, 0) x (0, 1, 0) in component "Pi case"
sketch "Sketch11 (2)" plane through (38.2, 0, 0) normal (1, 0, 0) x (0, 0, -1) in component "Pi case"
  line L0 (17.6, 130) -> (17.6, 155)
  arc A0 (17.6, 155) -> (16.6, 156) centre (16.6, 155) ccw
  line L1 (16.6, 156) -> (9.4, 156)
  arc A1 (9.4, 156) -> (8.4, 155) centre (9.4, 155) ccw
  line L2 (8.4, 155) -> (8.4, 130)
  arc A2 (8.4, 130) -> (9.4, 129) centre (9.4, 130) ccw
  line L3 (9.4, 129) -> (16.6, 129)
  arc A3 (16.6, 129) -> (17.6, 130) centre (16.6, 130) ccw
extrude "PCIe and power button" cut sketch "Sketch11 (2)" along normal mid plane 4 bodies 8 in component "Pi case"
ref_plane "WorkPlane12" through (0, 0, -24) normal (0, 0, 1) x (1, 0, 0) in component "Pi case"
sketch "Sketch12 (2)" plane through (0, 0, -24) normal (0, 0, 1) x (1, 0, 0) in component "Pi case"
  line L0 (37.2, 97) -> (45.2, 97)
  line L1 (45.2, 97) -> (45.2, 107)
  line L2 (45.2, 107) -> (37.2, 107)
  line L3 (37.2, 107) -> (37.2, 97)
  line L4 (126.2, 97) -> (134.2, 97)
  line L5 (134.2, 97) -> (134.2, 107)
  line L6 (134.2, 107) -> (126.2, 107)
  line L7 (126.2, 107) -> (126.2, 97)
  line L8 (37.2, 169) -> (45.2, 169)
  line L9 (45.2, 169) -> (45.2, 179)
  line L10 (45.2, 179) -> (37.2, 179)
  line L11 (37.2, 179) -> (37.2, 169)
  line L12 (126.2, 169) -> (134.2, 169)
  line L13 (134.2, 169) -> (134.2, 179)
  line L14 (134.2, 179) -> (126.2, 179)
  line L15 (126.2, 179) -> (126.2, 169)
extrude "Amp posts" add sketch "Sketch12 (2)" along normal mid plane 48 bodies 8 in component "Pi case"
ref_plane "WorkPlane13" through (0, 0, -45.25) normal (0, 0, 1) x (1, 0, 0) in component "Pi case"
sketch "Sketch13 (2)" plane through (0, 0, -45.25) normal (0, 0, 1) x (1, 0, 0) in component "Pi case"
  circle A0 centre (41.2, 101) radius 2
  circle A1 centre (130.2, 101) radius 2
  circle A2 centre (41.2, 175) radius 2
  circle A3 centre (130.2, 175) radius 2
extrude "Amp post inserts" cut sketch "Sketch13 (2)" along normal mid plane 7.5 bodies 8 in component "Pi case"
ref_plane "WorkPlane1" through (0, 0, -49.5) normal (0, 0, 1) x (1, 0, 0) in component "Amp plate"
sketch "Sketch1 (9)" plane through (0, 0, -49.5) normal (0, 0, 1) x (1, 0, 0) in component "Amp plate"
  line L0 (24.2, 93.5) -> (147.2, 93.5)
  arc A0 (147.2, 93.5) -> (151.2, 97.5) centre (147.2, 97.5) ccw
  line L1 (151.2, 97.5) -> (151.2, 178.5)
  arc A1 (151.2, 178.5) -> (147.2, 182.5) centre (147.2, 178.5) ccw
  line L2 (147.2, 182.5) -> (24.2, 182.5)
  arc A2 (24.2, 182.5) -> (20.2, 178.5) centre (24.2, 178.5) ccw
  line L3 (20.2, 178.5) -> (20.2, 97.5)
  arc A3 (20.2, 97.5) -> (24.2, 93.5) centre (24.2, 97.5) ccw
extrude "Plate" add sketch "Sketch1 (9)" along normal mid plane 3 separate body makes body 9 in component "Amp plate"
ref_plane "WorkPlane2" through (0, 0, -67.25) normal (0, 0, 1) x (1, 0, 0) in component "Amp plate"
sketch "Sketch2 (9)" plane through (0, 0, -67.25) normal (0, 0, 1) x (1, 0, 0) in component "Amp plate"
  circle A0 centre (26.7, 100) radius 4
  circle A1 centre (144.7, 100) radius 4
  circle A2 centre (26.7, 176) radius 4
  circle A3 centre (144.7, 176) radius 4
extrude "Amp standoffs" add sketch "Sketch2 (9)" along normal mid plane 33.5 bodies 9 in component "Amp plate"
ref_plane "WorkPlane3" through (0, 0, -82.25) normal (0, 0, 1) x (1, 0, 0) in component "Amp plate"
sketch "Sketch3 (9)" plane through (0, 0, -82.25) normal (0, 0, 1) x (1, 0, 0) in component "Amp plate"
  circle A0 centre (26.7, 100) radius 1.6
  circle A1 centre (144.7, 100) radius 1.6
  circle A2 centre (26.7, 176) radius 1.6
  circle A3 centre (144.7, 176) radius 1.6
extrude "Amp insert holes" cut sketch "Sketch3 (9)" along normal mid plane 5.5 bodies 9 in component "Amp plate"
ref_plane "WorkPlane4" through (0, 0, -49.5) normal (0, 0, 1) x (1, 0, 0) in component "Amp plate"
sketch "Sketch4 (9)" plane through (0, 0, -49.5) normal (0, 0, 1) x (1, 0, 0) in component "Amp plate"
  circle A0 centre (41.2, 101) radius 1.7
  circle A1 centre (130.2, 101) radius 1.7
  circle A2 centre (41.2, 175) radius 1.7
  circle A3 centre (130.2, 175) radius 1.7
extrude "Post screw holes" cut sketch "Sketch4 (9)" along normal mid plane 5 bodies 9 in component "Amp plate"
ref_plane "WorkPlane5" through (0, 0, -52.75) normal (0, 0, 1) x (1, 0, 0) in component "Amp plate"
sketch "Sketch5 (5)" plane through (0, 0, -52.75) normal (0, 0, 1) x (1, 0, 0) in component "Amp plate"
  circle A0 centre (33.2, 112) radius 4
  circle A1 centre (138.2, 112) radius 4
  circle A2 centre (33.2, 164) radius 4
  circle A3 centre (138.2, 164) radius 4
extrude "Mean Well bosses" add sketch "Sketch5 (5)" along normal mid plane 4.5 bodies 9 in component "Amp plate"
ref_plane "WorkPlane6" through (0, 0, -52.25) normal (0, 0, 1) x (1, 0, 0) in component "Amp plate"
sketch "Sketch6 (4)" plane through (0, 0, -52.25) normal (0, 0, 1) x (1, 0, 0) in component "Amp plate"
  circle A0 centre (33.2, 112) radius 2
  circle A1 centre (138.2, 112) radius 2
  circle A2 centre (33.2, 164) radius 2
  circle A3 centre (138.2, 164) radius 2
extrude "Mean Well insert holes" cut sketch "Sketch6 (4)" along normal mid plane 7.5 bodies 9 in component "Amp plate"
ref_plane "WorkPlane7" through (0, 0, -49.5) normal (0, 0, 1) x (1, 0, 0) in component "Amp plate"
sketch "Sketch7 (4)" plane through (0, 0, -49.5) normal (0, 0, 1) x (1, 0, 0) in component "Amp plate"
  line L0 (52.7, 107.5) -> (52.7, 168.5)
  arc A0 (58.7, 168.5) -> (52.7, 168.5) centre (55.7, 168.5) ccw
  line L1 (58.7, 168.5) -> (58.7, 107.5)
  arc A1 (52.7, 107.5) -> (58.7, 107.5) centre (55.7, 107.5) ccw
  line L2 (67.7, 107.5) -> (67.7, 168.5)
  arc A2 (73.7, 168.5) -> (67.7, 168.5) centre (70.7, 168.5) ccw
  line L3 (73.7, 168.5) -> (73.7, 107.5)
  arc A3 (67.7, 107.5) -> (73.7, 107.5) centre (70.7, 107.5) ccw
  line L4 (82.7, 107.5) -> (82.7, 168.5)
  arc A4 (88.7, 168.5) -> (82.7, 168.5) centre (85.7, 168.5) ccw
  line L5 (88.7, 168.5) -> (88.7, 107.5)
  arc A5 (82.7, 107.5) -> (88.7, 107.5) centre (85.7, 107.5) ccw
  line L6 (97.7, 107.5) -> (97.7, 168.5)
  arc A6 (103.7, 168.5) -> (97.7, 168.5) centre (100.7, 168.5) ccw
  line L7 (103.7, 168.5) -> (103.7, 107.5)
  arc A7 (97.7, 107.5) -> (103.7, 107.5) centre (100.7, 107.5) ccw
  line L8 (112.7, 107.5) -> (112.7, 168.5)
  arc A8 (118.7, 168.5) -> (112.7, 168.5) centre (115.7, 168.5) ccw
  line L9 (118.7, 168.5) -> (118.7, 107.5)
  arc A9 (112.7, 107.5) -> (118.7, 107.5) centre (115.7, 107.5) ccw
extrude "Vents" cut sketch "Sketch7 (4)" along normal mid plane 5 bodies 9 in component "Amp plate"
ref_plane "WorkPlane1" through (0, 0, 27.69) normal (0, 0, 1) x (1, 0, 0) in component "Screen (reference)"
sketch "Sketch1 (10)" plane through (0, 0, 27.69) normal (0, 0, 1) x (1, 0, 0) in component "Screen (reference)"
  line L0 (-9.275, 108.75) -> (180.725, 108.75)
  arc A0 (180.725, 108.75) -> (182.725, 110.75) centre (180.725, 110.75) ccw
  line L1 (182.725, 110.75) -> (182.725, 225.75)
  arc A1 (182.725, 225.75) -> (180.725, 227.75) centre (180.725, 225.75) ccw
  line L2 (180.725, 227.75) -> (-9.275, 227.75)
  arc A2 (-9.275, 227.75) -> (-11.275, 225.75) centre (-9.275, 225.75) ccw
  line L3 (-11.275, 225.75) -> (-11.275, 110.75)
  arc A3 (-11.275, 110.75) -> (-9.275, 108.75) centre (-9.275, 110.75) ccw
extrude "Extrude1" add sketch "Sketch1 (10)" along normal mid plane 4.8 separate body makes body 10 in component "Screen (reference)"
ref_plane "WorkPlane2" through (0, 0, 21.995) normal (0, 0, 1) x (1, 0, 0) in component "Screen (reference)"
sketch "Sketch2 (10)" plane through (0, 0, 21.995) normal (0, 0, 1) x (1, 0, 0) in component "Screen (reference)"
  line L0 (31.765, 129.04) -> (139.765, 129.04)
  line L1 (139.765, 129.04) -> (139.765, 201.04)
  line L2 (139.765, 201.04) -> (31.765, 201.04)
  line L3 (31.765, 201.04) -> (31.765, 129.04)
extrude "Extrude2" add sketch "Sketch2 (10)" along normal mid plane 6.59 separate body makes body 11 in component "Screen (reference)"
ref_plane "WorkPlane1" through (0, 0, -9.8) normal (0, 0, 1) x (1, 0, 0) in component "Raspberry Pi 5 + DAC (reference)"
sketch "Sketch1 (11)" plane through (0, 0, -9.8) normal (0, 0, 1) x (1, 0, 0) in component "Raspberry Pi 5 + DAC (reference)"
  line L0 (46.2, 110) -> (125.2, 110)
  arc A0 (125.2, 110) -> (128.2, 113) centre (125.2, 113) ccw
  line L1 (128.2, 113) -> (128.2, 163)
  arc A1 (128.2, 163) -> (125.2, 166) centre (125.2, 163) ccw
  line L2 (125.2, 166) -> (46.2, 166)
  arc A2 (46.2, 166) -> (43.2, 163) centre (46.2, 163) ccw
  line L3 (43.2, 163) -> (43.2, 113)
  arc A3 (43.2, 113) -> (46.2, 110) centre (46.2, 113) ccw
extrude "Extrude1'" add sketch "Sketch1 (11)" along normal mid plane 1.6 separate body makes body 12 in component "Raspberry Pi 5 + DAC (reference)"
ref_plane "WorkPlane2" through (0, 0, -26.8) normal (0, 0, 1) x (1, 0, 0) in component "Raspberry Pi 5 + DAC (reference)"
sketch "Sketch2 (11)" plane through (0, 0, -26.8) normal (0, 0, 1) x (1, 0, 0) in component "Raspberry Pi 5 + DAC (reference)"
  line L0 (46.2, 110) -> (125.2, 110)
  arc A0 (125.2, 110) -> (128.2, 113) centre (125.2, 113) ccw
  line L1 (128.2, 113) -> (128.2, 163)
  arc A1 (128.2, 163) -> (125.2, 166) centre (125.2, 163) ccw
  line L2 (125.2, 166) -> (46.2, 166)
  arc A2 (46.2, 166) -> (43.2, 163) centre (46.2, 163) ccw
  line L3 (43.2, 163) -> (43.2, 113)
  arc A3 (43.2, 113) -> (46.2, 110) centre (46.2, 113) ccw
extrude "Extrude2'" add sketch "Sketch2 (11)" along normal mid plane 32.4 separate body makes body 13 in component "Raspberry Pi 5 + DAC (reference)"
ref_plane "WorkPlane1" through (0, 0, -84.8) normal (0, 0, 1) x (1, 0, 0) in component "Amp (reference)"
sketch "Sketch1 (12)" plane through (0, 0, -84.8) normal (0, 0, 1) x (1, 0, 0) in component "Amp (reference)"
  line L0 (25.2, 96.5) -> (146.2, 96.5)
  arc A0 (146.2, 96.5) -> (148.2, 98.5) centre (146.2, 98.5) ccw
  line L1 (148.2, 98.5) -> (148.2, 177.5)
  arc A1 (148.2, 177.5) -> (146.2, 179.5) centre (146.2, 177.5) ccw
  line L2 (146.2, 179.5) -> (25.2, 179.5)
  arc A2 (25.2, 179.5) -> (23.2, 177.5) centre (25.2, 177.5) ccw
  line L3 (23.2, 177.5) -> (23.2, 98.5)
  arc A3 (23.2, 98.5) -> (25.2, 96.5) centre (25.2, 98.5) ccw
extrude "Extrude1''" add sketch "Sketch1 (12)" along normal mid plane 1.6 separate body makes body 14 in component "Amp (reference)"
ref_plane "WorkPlane2" through (0, 0, -99.3) normal (0, 0, 1) x (1, 0, 0) in component "Amp (reference)"
sketch "Sketch2 (12)" plane through (0, 0, -99.3) normal (0, 0, 1) x (1, 0, 0) in component "Amp (reference)"
  line L0 (25.2, 96.5) -> (146.2, 96.5)
  arc A0 (146.2, 96.5) -> (148.2, 98.5) centre (146.2, 98.5) ccw
  line L1 (148.2, 98.5) -> (148.2, 177.5)
  arc A1 (148.2, 177.5) -> (146.2, 179.5) centre (146.2, 177.5) ccw
  line L2 (146.2, 179.5) -> (25.2, 179.5)
  arc A2 (25.2, 179.5) -> (23.2, 177.5) centre (25.2, 177.5) ccw
  line L3 (23.2, 177.5) -> (23.2, 98.5)
  arc A3 (23.2, 98.5) -> (25.2, 96.5) centre (25.2, 98.5) ccw
extrude "Extrude2''" add sketch "Sketch2 (12)" along normal mid plane 27.4 separate body makes body 15 in component "Amp (reference)"
ref_plane "WorkPlane1" through (0, 0, -67.5) normal (0, 0, 1) x (1, 0, 0) in component "Mean Well RSD-30G-5 (reference)"
sketch "Sketch1 (13)" plane through (0, 0, -67.5) normal (0, 0, 1) x (1, 0, 0) in component "Mean Well RSD-30G-5 (reference)"
  line L0 (30.2, 108) -> (141.2, 108)
  arc A0 (141.2, 108) -> (142.2, 109) centre (141.2, 109) ccw
  line L1 (142.2, 109) -> (142.2, 167)
  arc A1 (142.2, 167) -> (141.2, 168) centre (141.2, 167) ccw
  line L2 (141.2, 168) -> (30.2, 168)
  arc A2 (30.2, 168) -> (29.2, 167) centre (30.2, 167) ccw
  line L3 (29.2, 167) -> (29.2, 109)
  arc A3 (29.2, 109) -> (30.2, 108) centre (30.2, 109) ccw
extrude "Extrude1'''" add sketch "Sketch1 (13)" along normal mid plane 25 separate body makes body 16 in component "Mean Well RSD-30G-5 (reference)"
ref_plane "WorkPlane1" through (0, 0, 4.35) normal (0, 0, 1) x (1, 0, 0) in component "Climate controls (space)"
sketch "Sketch1 (14)" plane through (0, 0, 4.35) normal (0, 0, 1) x (1, 0, 0) in component "Climate controls (space)"
  line L0 (0, 0) -> (171.45, 0)
  line L1 (171.45, 0) -> (171.45, 81.55)
  line L2 (171.45, 81.55) -> (0, 81.55)
  line L3 (0, 81.55) -> (0, 0)
extrude "Extrude1''''" add sketch "Sketch1 (14)" along normal mid plane 8.7 separate body makes body 17 in component "Climate controls (space)"
ref_plane "WorkPlane1" through (-5.075, 0, 0) normal (1, 0, 0) x (0, 1, 0) in component "Factory radio brackets (placeholder)"
sketch "Sketch1 (15)" plane through (-5.075, 0, 0) normal (1, 0, 0) x (0, 0, -1) in component "Factory radio brackets (placeholder)"
  line L0 (70, 87) -> (70, 218)
  arc A0 (70, 218) -> (68, 220) centre (68, 218) ccw
  line L1 (68, 220) -> (20, 220)
  arc A1 (20, 220) -> (18, 218) centre (20, 218) ccw
  line L2 (18, 218) -> (18, 87)
  arc A2 (18, 87) -> (20, 85) centre (20, 87) ccw
  line L3 (20, 85) -> (68, 85)
  arc A3 (68, 85) -> (70, 87) centre (68, 87) ccw
extrude "Extrude1'''''" add sketch "Sketch1 (15)" along normal mid plane 1.6 separate body makes body 18 in component "Factory radio brackets (placeholder)"